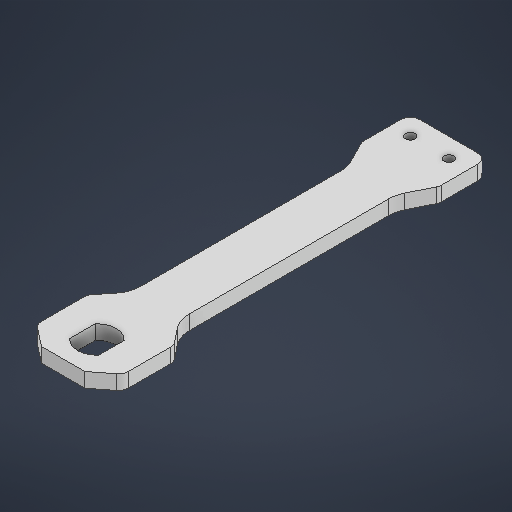
# Autodesk Inventor part: thanh lk 1
Saved by Autodesk Inventor 2027 (Build 310192060, 192F)
## iProperties
Created: 2026-08-19
Part Number: thanh lk 1
Material: Generic
Document SubType Name: Modeling
Designer: thita
Density: 1 g/cm^3
Appearance: Default
Author: thita
Autodesk Inventor part; units mm, degrees
ref_plane "YZ Plane" through (0, 0, 0) normal (1, 0, 0) x (0, 1, 0)
ref_plane "XZ Plane" through (0, 0, 0) normal (0, 1, 0) x (-1, 0, 0)
ref_plane "XY Plane" through (0, 0, 0) normal (0, 0, 1) x (1, 0, 0)
sketch "Sketch1" plane through (0, 0, 0) normal (0, 1, 0) x (-1, 0, 0)
  line L0 (3, -2.6458) -> (3, 2.6458)
  arc A0 (3, 2.6458) -> (-3, 2.6458) centre (0, 0) ccw
  arc A1 (-3, -2.6458) -> (3, -2.6458) centre (0, 0) ccw
  line L1 (-3, 2.6458) -> (-3, -2.6458)
  line L2 (-9, -6.2984) -> (-9, 2.5218)
  line L3 (-9, 7) -> (9, -7) construction
  line L4 (9, 7) -> (-9, -7) construction
  circle A2 centre (4, -69) radius 1
  circle A3 centre (-4, -69) radius 1
  line L5 (5, -14.1047) -> (5, -55.5836)
  line L6 (-5, -14.1047) -> (-5, -55.5836)
  line L7 (-6, -73) -> (6, -73)
  line L8 (8, -73) -> (-8, -73)
  line L9 (-8, -71) -> (-8, -63.4721)
  line L10 (8, -63.4721) -> (8, -71)
  arc A4 (6, -73) -> (8, -71) centre (6, -71) ccw
  arc A5 (-8, -71) -> (-6, -73) centre (-6, -71) ccw
  line L11 (7.7889, -62.5777) -> (5.6334, -58.2669)
  line L12 (-7.7889, -62.5777) -> (-5.6334, -58.2669)
  arc A6 (5, -55.5836) -> (5.6334, -58.2669) centre (11, -55.5836) ccw
  arc A7 (-5.6334, -58.2669) -> (-5, -55.5836) centre (-11, -55.5836) ccw
  arc A8 (8, -63.4721) -> (7.7889, -62.5777) centre (6, -63.4721) ccw
  arc A9 (-7.7889, -62.5777) -> (-8, -63.4721) centre (-6, -63.4721) ccw
  line L13 (8.5617, -7.5478) -> (6.3148, -10.3565)
  line L14 (-8.5617, -7.5478) -> (-6.3148, -10.3565)
  arc A10 (6.3148, -10.3565) -> (5, -14.1047) centre (11, -14.1047) ccw
  arc A11 (-5, -14.1047) -> (-6.3148, -10.3565) centre (-11, -14.1047) ccw
  arc A12 (8.5617, -7.5478) -> (9, -6.2984) centre (7, -6.2984) ccw
  arc A13 (-9, -6.2984) -> (-8.5617, -7.5478) centre (-7, -6.2984) ccw
  line L15 (-8.2279, 4.1005) -> (-4.5, 7)
  arc A14 (-8.2279, 4.1005) -> (-9, 2.5218) centre (-7, 2.5218) ccw
  line L16 (0, 7) -> (-4.5, 7)
  line L17 (8.2279, 4.1005) -> (4.5, 7)
  arc A15 (9, 2.5218) -> (8.2279, 4.1005) centre (7, 2.5218) ccw
  line L18 (0, 7) -> (4.5, 7)
  line L19 (9, 2.5218) -> (9, -6.2984)
  line L20 (0, -73) -> (0, -69)
  line L21 (4, -69) -> (-4, -69)
  line L22 (0, -69) -> (0, -67.6991)
  point P0 (0, 0)
  point P1 (-8, -63)
  point P2 (-5, -57)
  point P3 (-9, 3.5)
  point P4 (9, 3.5)
  dimension "d0" = 18
  dimension "d1" = 14
  dimension "d2" = 69
  dimension "d4" = 2
  dimension "d5" = 2
  dimension "d10" = 10
  dimension "d11" = 2
  dimension "d12" = 2
  dimension "d14" = 6
  dimension "d15" = 2
  dimension "d18" = 6
  dimension "d19" = 2
  dimension "d20" = 2
  constraints: 46 end point, 28 point on circle, 21 tangent, 16 centre point, 13 point on line, 4 equal radius, 4 midpoint, 2 horizontal, 2 vertical, 1 parallel, 1 perpendicular
  measures "d0" distance of L3.start L4.start
  measures "d1" distance of L4.start L3.end
  measures "d2" distance of A1.centre L20.end
  measures "d4" diameter of A2
  measures "d5" diameter of A3
  measures "d10" distance of L8.end point (-8, -63)
  measures "d11" radius of A4
  measures "d12" radius of A5
  measures "d14" radius of A6
  measures "d15" radius of A8
  measures "d18" radius of A10
  measures "d19" radius of A12
  measures "d20" radius of A14
extrude "Extrusion1" add sketch "Sketch1" along normal blind 3
sketch "Sketch2" plane through (5, 0, -14.1047) normal (1, 0, 0) x (0, 0, -1)
  line L0 (0, 0) -> (0, 3) projected
  line L1 (0, 0.25) -> (0, 2.75)
  line L2 (41.4789, 0) -> (41.4789, 3) projected
  line L3 (40.2289, 1.5) -> (42.7289, 1.5)
  line L4 (0, 2.75) -> (41.4789, 2.75)
  line L5 (41.4789, 2.75) -> (41.4789, 3)
  line L6 (41.4789, 3) -> (0, 3)
  line L7 (0, 3) -> (0, 2.75)
  line L8 (0, 0) -> (41.4789, 0) projected
  line L9 (0, 0.25) -> (41.4789, 0.25)
  line L10 (41.4789, 0.25) -> (41.4789, 0)
  line L11 (41.4789, 0) -> (0, 0)
  line L12 (0, 0) -> (0, 0.25)
  point P0 (-14.1047, 0)
  point P1 (0, 1.5)
  point P2 (41.4789, 1.5)
  point P3 (0, 0.25)
  point P4 (0, 3)
  dimension "d23" = 2.5
  dimension "d24" = 2.5
  constraints: 20 end point, 4 midpoint, 4 parallel, 3 horizontal, 2 perpendicular, 1 point on line
  measures "d23" distance of L1.start L1.end
  measures "d24" distance of L3.start L3.end
extrude "Extrusion2" [suppressed]
fillet "Fillet1" [suppressed]
fillet "Fillet2" [suppressed]
sketch "Sketch3" plane through (5, 3.75, -15.5414) normal (0, 1, 0) x (1, 0, 0)
  line L0 (0, 0) -> (-10, 0) projected
  line L1 (-5, 0) -> (-5, 38.6055)
  line L2 (-10, 38.6055) -> (0, 38.6055) projected
  line L3 (-10, 0) -> (-10, 38.6055) projected
  line L4 (-8.75, 1.8028) -> (-8.75, 36.8028)
  line L5 (-6.25, 36.8028) -> (-6.25, 1.8028)
  line L6 (-6.25, 1.8028) -> (-8.75, 1.8028)
  line L7 (-3.75, 36.8028) -> (-3.75, 1.8028)
  line L8 (-3.75, 1.8028) -> (-1.25, 1.8028)
  line L9 (-1.25, 1.8028) -> (-1.25, 36.8028)
  line L10 (-1.25, 36.8028) -> (-3.75, 36.8028)
  line L11 (-8.75, 36.8028) -> (-6.25, 36.8028)
  point P0 (-5, -15.5414)
  point P1 (-7.5, 36.8028)
  dimension "d33" = 2.5
  constraints: 18 end point, 2 midpoint, 2 parallel, 2 symmetric about line, 1 horizontal, 1 perpendicular, 1 vertical
  measures "d33" distance of L8.end L7.end
extrude "Extrusion3" [suppressed]
chamfer "Chamfer1" [suppressed]
body "Solid1"
